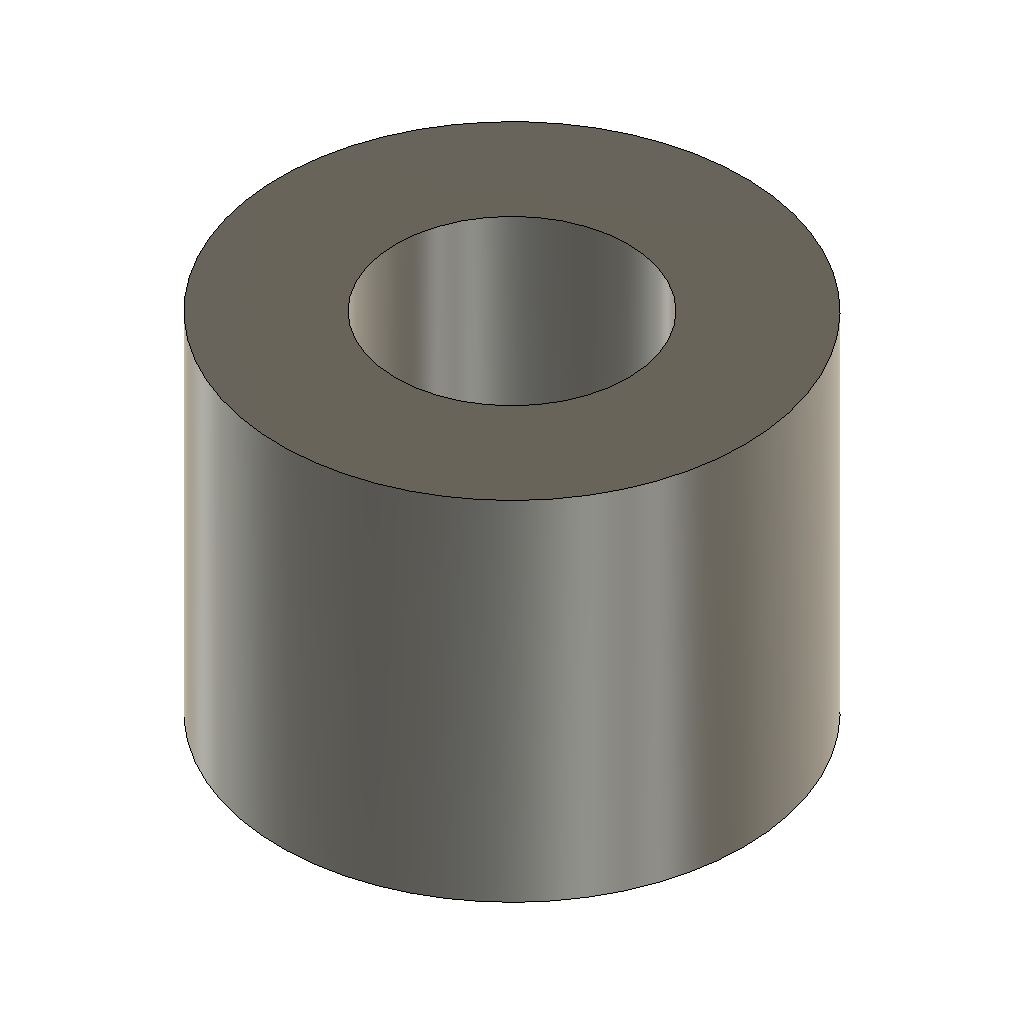
f2sc-test-revolve-stale (Autodesk Fusion 360 design; units mm, degrees)
part number: 2026-11-27-13-42-23-777
Autodesk Fusion 360 part; units mm, degrees
sketch "Sketch1" plane through (0, 0, 0) normal (0, 1, 0) x (1, 0, 0)
  line L0 (0, 0) -> (10, 0)
  line L1 (10, 0) -> (10, -30)
  line L2 (10, -30) -> (0, -30)
  line L3 (0, -30) -> (0, 0)
  line L4 (10, 0) -> (20, 0)
  line L5 (20, 0) -> (20, -30)
  line L6 (20, -30) -> (10, -30)
  line L7 (10, -30) -> (10, 0)
  line L8 (13.0089, -30) -> (16.0089, -30)
  line L9 (16.0089, -30) -> (16.0089, -27)
  line L10 (16.0089, -27) -> (13.0089, -27)
  line L11 (13.0089, -27) -> (13.0089, -30)
  dimension "d1" = 10
  dimension "d2" = 30
  dimension "d3" = 10
  dimension "d4" = 30
  dimension "d6" = 3
  dimension "d7" = 3
  constraint horizontal L0
  constraint vertical L1
  constraint horizontal L2
  constraint vertical L3
  constraint coincident L0.start L3.end
  constraint horizontal L4
  constraint vertical L5
  constraint horizontal L6
  constraint vertical L7
  constraint horizontal L8
  constraint vertical L9
  constraint horizontal L10
  constraint vertical L11
  constraint coincident L6 L8.start
  measures "d1" distance of L0.start L0.end
  measures "d2" distance of L0.start L2.end
  measures "d3" distance of L0.end L4.end
  measures "d4" distance of L0.end L1.end
  measures "d6" distance of L8.start L8.end
  measures "d7" distance of L8.start L10.end
revolve "Revolve1" add sketch "Sketch1" angle 360 about axis through (0, 0, 30) along (0, 0, -1) contours L1 L4 L5 L6 L7 L9 L10 L11 | L6 L8 L9 L10 L11
